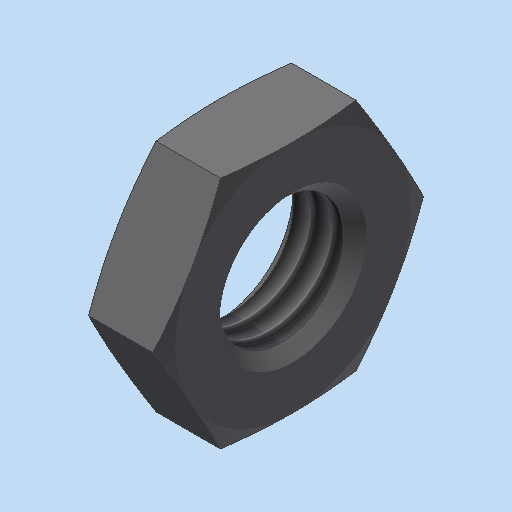
# Autodesk Inventor part: Sechskantmutter_DIN_439_B___M12
Saved by Autodesk Inventor 2023.3 (Build 273359000, 359)
## iProperties
Shininess: 64.0
Length Units: 11269
Angle Units: 11279
Time Units: 11290
Mass Units: 11283
Length Display Precision: 3
Angle Display Precision: 2
Compacted: True
Part Number: Sechskantmutter_DIN_439_B___M12
Document SubType Name: Modeling
Created: 2004-03-22
Material: xStahl_AnP_Dummymaterial
Description: =<RBPARTNOTITLE2>
Vendor: NORM8
Designer: S.Riedelsheimer
Manufacturer: Standard
Standards Organization: Custom
Density: 7.85 g/cm^3
Mass: 10.6553 g
Surface Area: 10.0163 cm^2
Volume: 1.35737 cm^3
Appearance: Stahl - normal AnP
Density: 0.0
Volumn: 0.0
Area: 0.0
PropertySet Name: Model Information
Control State: 0
Master: False
Checked Out: False
CNS_NB: Sechskantmutter DIN 439-B - M12
CNS_NN: DIN 439 B
CNS_NT: Sechskantmutter, niedrige Form
CNS_NBSYN: Sechskantmutter DIN 439-B - $NENN.
CNS_LINA: Sechskantmutter DIN 439-B - M12
CNS_NENN: M12
CNS_D: 12.000
CNS_D1: 10.106
CNS_P: 1.750
CNS_M: 6.000
CNS_S: 19.000
CNS_KT: X
PSOL_IDENT_0: {C:\partsolutions8\data\23d-libs\bosch_bamberg\muttern\sechskantmuttern\din_439_form_b.prj},169 {M=N
PSOL_IDENT_1: enngewinde},{VTYP=3D},{NB=Sechskantmutter DIN 439-B - M12},{NN=DIN 439 B},{DATE=26.11.2003},{GEOMDAT
PSOL_IDENT_2: E=26.11.2003},{VERSION=v1},{LINEID=130},{LINESUBID=-1},{WBVAR=}  {NB=Sechskantmutter DIN 439-B - M12
PSOL_IDENT_3: },{LINA=Sechskantmutter DIN 439-B - M12},{KT=X},{IDNR=},{NENN=M12},{D=12.000},{D1=10.106},{P=1.750},
PSOL_IDENT_4: {M=6.000},{S=19.000}
RBPARTNOTITLE2: Sechskantmutter, niedrige Form
RBPARTNOTITLE1: hexagon thin nut
RBPARTMADEOF: DIN 439-B - M12
RBDRAWINGMISSINGSPEC: --
AnP_Kategorie: 5
Title: Sechskantmutter DIN 439-B - M12
Author: S.Riedelsheimer
Keywords: =<RBPARTMADEOF>
Comments: =<RBSURFACE2>
Revision Number: 01
Autodesk Inventor part; units mm, degrees
sketch "Sketch_1" plane through (0, 0, 0) normal (0, 0, 1) x (1, 0, 0)
  line L0 (6, 0) -> (0, 0)
  line L1 (0, 6) -> (0.947, 5.053)
  line L2 (0.947, 5.053) -> (5.053, 5.053)
  line L3 (5.053, 5.053) -> (6, 6)
  line L4 (6, 6) -> (6, 9.5)
  line L5 (6, 9.5) -> (3, 20.6962)
  line L6 (3, 20.6962) -> (0, 9.5)
  line L7 (0, 9.5) -> (0, 6)
  constraints: 16 end point
revolve "Drehung1" add sketch "Sketch_1" angle 360 about axis through (6, 0, 0) along (-1, 0, 0)
thread "Gewinde1" size "M12x1.75" class "6H" standard "ANSI Metric M Profile" length 6
sketch "Sketch_2" plane through (0, 0, 0) normal (1, 0, 0) x (0, 1, 0)
  line L0 (-38, 38) -> (-38, -38)
  line L1 (-38, -38) -> (38, -38)
  line L2 (38, -38) -> (38, 38)
  line L3 (38, 38) -> (-38, 38)
  line L4 (5.4848, 9.5) -> (-5.4848, 9.5)
  line L5 (-5.4848, 9.5) -> (-10.9697, 0)
  line L6 (-10.9697, 0) -> (-5.4848, -9.5)
  line L7 (-5.4848, -9.5) -> (5.4848, -9.5)
  line L8 (5.4848, -9.5) -> (10.9697, 0)
  line L9 (10.9697, 0) -> (5.4848, 9.5)
  constraints: 20 end point
extrude "Extrusion1" cut sketch "Sketch_2" along normal mid plane 14
ref_plane "IP1_XY" through (0, 0, 0) normal (1, 0, 0) x (0, 0, -1)
ref_plane "IP1_YZ" through (0, 0, 0) normal (0, 0, -1) x (0, 1, 0)
ref_plane "IP2_XY" through (6, 0, 0) normal (1, 0, 0) x (0, 0, -1)
ref_plane "IP2_YZ" through (6, 0, 0) normal (0, 0, -1) x (0, 1, 0)
